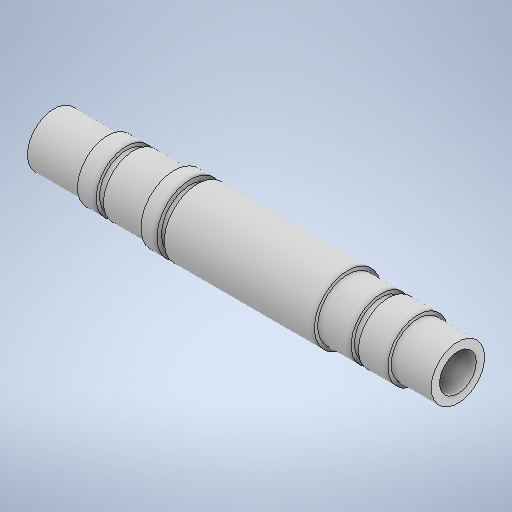
# Autodesk Inventor part: Nakrętka
Saved by Autodesk Inventor 2025.2 (Build 292293000, 293)
## iProperties
Created: 2025-04-06
Part Number: Nakrętka
Material: Generic
Document SubType Name: Modeling
Designer: makst
Density: 1 g/cm^3
Appearance: Default
Author: makst
Autodesk Inventor part; units mm, degrees
ref_plane "YZ Plane" through (0, 0, 0) normal (1, 0, 0) x (0, 1, 0)
ref_plane "XY Plane" through (0, 0, 0) normal (0, 0, 1) x (1, 0, 0)
sketch "Sketch1" plane through (0, 0, 0) normal (0, 1, 0) x (-1, 0, 0)
  line L0 (0, 0) -> (9.8696, 0)
  line L1 (0, -4.5) -> (10.5, -4.5)
  line L2 (10.5, -4.5) -> (10.5, -5)
  line L3 (10.5, -5) -> (36.5, -5)
  line L4 (36.5, -5) -> (36.5, -4.5)
  line L5 (36.5, -4.5) -> (46.5, -4.5)
  line L6 (46.5, -4.5) -> (46.5, -4)
  line L7 (46.5, -4) -> (54.5, -4)
  line L8 (0, -4.5) -> (0, 0)
  line L9 (54.5, -4) -> (54.5, 0)
  line L10 (54.5, 0) -> (0, 0)
  line L11 (0, -4.5) -> (5.5, -4.5)
  line L12 (5.5, -4.5) -> (5.5, -4)
  line L13 (5.5, -4) -> (4.4, -4)
  line L14 (4.4, -4) -> (4.4, -4.5)
  line L15 (46.5, -4.5) -> (43.7, -4.5)
  line L16 (43.7, -4.5) -> (43.7, -4)
  line L17 (43.7, -4) -> (42.6, -4)
  line L18 (42.6, -4) -> (42.6, -4.5)
  line L19 (0, -4) -> (-6, -4)
  line L20 (-6, -4) -> (-6, 0)
  line L21 (-6, 0) -> (0, 0)
  point P0 (50.5, -4)
  point P1 (27.536, 0)
  point P2 (54.5, -2)
  point P3 (28.3546, 0)
  point P4 (29.5527, -5)
  dimension "d0" = 10.5
  dimension "d4" = 9
  dimension "d6" = 26
  dimension "d8" = 10
  dimension "d10" = 8
  dimension "d11" = 10
  dimension "d12" = 9
  dimension "d13" = 8
  dimension "d25" = 5.5
  dimension "d26" = 0.5
  dimension "d27" = 1.1
  dimension "d28" = 2.8
  dimension "d29" = 0.5
  dimension "d30" = 1.1
  dimension "d49" = 4
  dimension "d50" = 6
  constraints: 44 end point, 12 perpendicular, 8 point on line, 6 horizontal, 3 vertical, 2 midpoint
  measures "d0" distance of L1.start L1.end
  measures "d4" diameter of L1 L0
  measures "d6" distance of L2.end L3.end
  measures "d8" distance of L4.end L5.end
  measures "d10" distance of L6.end L7.end
  measures "d11" diameter of L3 L0
  measures "d12" diameter of L5 L0
  measures "d13" diameter of point (50.5, -4) L0
  measures "d25" distance of L1.start L11.end
  measures "d26" distance of L11.end L12.end
  measures "d27" distance of L12.end L13.end
  measures "d28" distance of L5.end L15.end
  measures "d29" distance of L15.end L16.end
  measures "d30" distance of L16.end L17.end
  measures "d49" distance between parallel lines of L10 L19
  measures "d50" distance of L19.start L19.end
revolve "Revolution1" add sketch "Sketch1" angle 360 about axis through (0, 0, 0) along (-1, 0, 0) contours L0 L10 L9 L7 L6 L5 L16 L17 L18 L4 L3 L2 L1 L12 L13 L14 L8 | L8 L19 L20 L21
sketch "Sketch2" plane through (-54.5, 0, 0) normal (-1, 0, 0) x (0, 0, 1)
  point P0 (0, 0)
hole "Hole1" at (-54.5, 0, 0) direction (1, 0, 0) diameter 4.134 depth 24 thread size "M5x0.8" class "6H" standard "ISO Metric profile"
chamfer "Chamfer1" distance 0.5 angle 45 1 edges at (-54.5, 0, -2.067)
ref_plane "Work Plane1" through (-23.5, -5, 0) normal (0, 1, 0) x (-1, 0, 0)
sketch "Sketch3" plane through (-23.5, -5, 0) normal (0, 1, 0) x (-1, 0, 0)
  line L0 (31, -4) -> (31, 4) projected
  line L1 (-13, 5) -> (13, 5) projected
  line L2 (-13, -5) -> (13, -5) projected
  arc A0 (5, -0.5) -> (5, 0.5) centre (5, 0) ccw
  arc A1 (3.5, 0.5) -> (3.5, -0.5) centre (3.5, 0) ccw
  line L3 (3.5, -0.5) -> (5, -0.5)
  line L4 (3.5, 0.5) -> (5, 0.5)
  point P0 (-23.5, 0)
  dimension "d33" = 26
  dimension "d35" = 1
  dimension "d36" = 1
  dimension "d51" = 1.5
  constraints: 4 end point, 4 point on circle, 4 tangent, 2 centre point, 2 coincident
  measures "d33" distance from line of point (5, 0) L0
  measures "d35" diameter of A0
  measures "d36" diameter of A1
  measures "d51" distance of A1.centre A0.centre
extrude "Extrusion1" cut sketch "Sketch3" along normal blind 1.5
sketch "Sketch4" plane through (0, 0, 0) normal (0, 1, 0) x (-1, 0, 0)
  line L0 (10.5, -5) -> (36.5, -5) projected
  line L1 (54.5, -4) -> (54.5, 4) projected
  line L2 (33, -5) -> (34.1, -5)
  line L3 (34.1, -5) -> (34.1, -4.3)
  line L4 (34.1, -4.3) -> (33, -4.3)
  line L5 (33, -4.3) -> (33, -5)
  line L6 (54.5, 0) -> (61.7069, 0)
  point P0 (0, 0)
  dimension "d42" = 21.5
  dimension "d43" = 1.1
  dimension "d44" = 0.7
  constraints: 10 end point, 2 perpendicular, 2 point on line, 1 horizontal, 1 midpoint, 1 parallel
  measures "d42" distance from line of L1 L2.start
  measures "d43" distance of L2.start L2.end
  measures "d44" distance of L2.end L3.end
revolve "Revolution2" cut sketch "Sketch4" angle 360 about axis through (-54.5, 0, 0) along (-1, 0, 0)
sketch "Sketch5" plane through (-23.5, -5, 0) normal (0, 1, 0) x (-1, 0, 0)
  line L0 (-13, 5) -> (9.5, 5) projected
  line L1 (-13, 5) -> (-9, 5)
  line L2 (-13, -5) -> (9.5, -5) projected
  line L3 (-13, -5) -> (-13, 5) projected
  line L4 (-9, 5) -> (-9, -5)
  line L5 (-9, -5) -> (-13, -5)
  line L6 (-13, 5) -> (-13, -5)
  line L7 (-6, 5) -> (-6, -5)
  point P0 (-23.5, 0)
  dimension "d46" = 4
  dimension "d59" = 7
  constraints: 10 end point, 5 point on line, 2 collinear, 2 perpendicular
  measures "d46" distance of L1.start L1.end
  measures "d59" distance between parallel lines of L3 L7
extrude "Extrusion2" cut sketch "Sketch5" along normal blind 0.5 contours L0 L7 L2 L4
sketch "Sketch6" plane through (-30.5, 0, 0) normal (-1, 0, 0) x (0, 0, 1)
  point P0 (0, 0)
  point P1 (0, 0)
  constraints: 1 coincident
hole "Hole2" at (-30.5, 0, 0) direction (1, 0, 0) diameter 5.5 end through all clearance for "Countersunk Flat Head Screw ISO 2009/7046" size "M5" standard "ISO"
body "Solid1"
